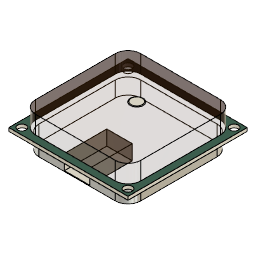
RaspberryPI5 Case + LoraWan1302 Hat (Autodesk Fusion 360 archive; units mm, degrees)
design "Beitian BE-280 GPS/GNSS Module"
Autodesk Fusion 360 part; units mm, degrees
sketch "Sketch1" plane through (0, 0, 0) normal (0, 0, 1) x (1, 0, 0)
  line L0 (0, 0) -> (28.1, 0)
  line L1 (28.1, 0) -> (28.1, 28.1)
  line L2 (28.1, 28.1) -> (0, 28.1)
  line L3 (0, 28.1) -> (0, 0)
  circle A0 centre (1.55, 26.55) radius 1
  circle A1 centre (26.55, 26.55) radius 1
  circle A2 centre (1.55, 1.55) radius 1
  circle A3 centre (26.55, 1.55) radius 1
  dimension "d1" = 28.1
  dimension "d2" = 28.1
  dimension "d3" = 2
  dimension "d4" = 2
  dimension "d5" = 2
  dimension "d6" = 2
  dimension "d7" = 25
  dimension "d8" = 25
  dimension "d9" = 25
  dimension "d10" = 25
  dimension "d11" = 1.55
  dimension "d12" = 1.55
  constraint horizontal L0
  constraint vertical L1
  constraint horizontal L2
  constraint vertical L3
  constraint coincident L0.start L3.end
  measures "d1" distance of L0.start L0.end
  measures "d2" distance of L0.start L2.end
  measures "d3" diameter of A0
  measures "d4" diameter of A1
  measures "d5" diameter of A2
  measures "d6" diameter of A3
  measures "d7" distance of A0.centre A1.centre
  measures "d8" distance of A0.centre A2.centre
  measures "d9" horizontal distance of A2.centre A3.centre
  measures "d10" distance of A1.centre A3.centre
  measures "d11" distance of L1 A1.centre
  measures "d12" distance of L2 A1.centre
extrude "Extrude1" add sketch "Sketch1" along normal blind 0.8
sketch "Sketch2" plane through (0, 0, 0.8) normal (0, 0, 1) x (-1, 0, 0)
  circle A0 centre (-26.55, -1.55) radius 1
  circle A1 centre (-1.55, -26.55) radius 1
  circle A2 centre (-26.55, -26.55) radius 1
  circle A3 centre (-1.55, -1.55) radius 1
  line L0 (0, -28.1) -> (0, 0)
  line L1 (0, 0) -> (-28.1, 0)
  line L2 (-28.1, 0) -> (-28.1, -28.1)
  line L3 (-28.1, -28.1) -> (0, -28.1)
  line L4 (-4.65, -26.45) -> (-23.45, -26.45)
  line L5 (-26.45, -23.45) -> (-26.45, -4.65)
  line L6 (-23.45, -1.65) -> (-4.65, -1.65)
  line L7 (-1.65, -4.65) -> (-1.65, -23.45)
  arc A4 (-4.65, -26.45) -> (-1.65, -23.45) centre (-4.65, -23.45) ccw
  arc A5 (-26.45, -23.45) -> (-23.45, -26.45) centre (-23.45, -23.45) ccw
  arc A6 (-23.45, -1.65) -> (-26.45, -4.65) centre (-23.45, -4.65) ccw
  arc A7 (-1.65, -4.65) -> (-4.65, -1.65) centre (-4.65, -4.65) ccw
  point P0 (-1.65, -26.45)
  point P1 (-26.45, -26.45)
  point P2 (-1.65, -1.65)
  dimension "d15" = 24.8
  dimension "d16" = 24.8
  dimension "d17" = 1.65
  dimension "d18" = 1.65
  dimension "d19" = 3
  dimension "d20" = 3
  constraint horizontal L4
  constraint vertical L5
  constraint horizontal L6
  constraint vertical L7
  constraint coincident P0 L4
  constraint coincident P0 L7
  constraint tangent L4 A4
  constraint tangent L7 A4
  constraint coincident P1 L4
  constraint coincident P1 L5
  constraint tangent L4 A5
  constraint tangent L5 A5
  constraint equal A4 A5
  constraint tangent L5 A6
  constraint tangent L6 A6
  constraint equal A4 A6
  constraint coincident P2 L6
  constraint coincident P2 L7
  constraint tangent L6 A7
  constraint tangent L7 A7
  measures "d15" distance of P0 P1
  measures "d16" distance of P0 P2
  measures "d17" distance of L3 L4
  measures "d18" distance of L0 L7
  measures "d19" radius of A4
  measures "d20" radius of A7
extrude "Extrude2" add sketch "Sketch2" along normal blind 4.2 contours L4 L5 L6 L7 A4 A5 A6 A7
sketch "Sketch3" plane through (0, 0, 5) normal (0, 0, 1) x (-1, 0, 0)
  arc A0 (-4.65, -26.45) -> (-1.65, -23.45) centre (-4.65, -23.45) ccw
  line L0 (-1.65, -23.45) -> (-1.65, -4.65)
  arc A1 (-1.65, -4.65) -> (-4.65, -1.65) centre (-4.65, -4.65) ccw
  line L1 (-4.65, -1.65) -> (-23.45, -1.65)
  arc A2 (-23.45, -1.65) -> (-26.45, -4.65) centre (-23.45, -4.65) ccw
  line L2 (-26.45, -4.65) -> (-26.45, -23.45)
  arc A3 (-26.45, -23.45) -> (-23.45, -26.45) centre (-23.45, -23.45) ccw
  line L3 (-23.45, -26.45) -> (-4.65, -26.45)
  circle A4 centre (-14.05, -16.1) radius 1.5
  line L4 (-28.1, -28.1) -> (0, -28.1)
  line L5 (-28.1, 0) -> (-28.1, -28.1)
  dimension "d23" = 3
  dimension "d24" = 12
  dimension "d25" = 14.05
  measures "d23" diameter of A4
  measures "d24" distance of A4.centre L4
  measures "d25" distance of A4.centre L5
extrude "Extrude3" add sketch "Sketch3" along normal blind 0.1 contours A4
sketch "Sketch4" plane through (0, 0, 0) normal (0, 0, -1) x (1, 0, 0)
  circle A0 centre (26.55, -1.55) radius 1
  circle A1 centre (1.55, -26.55) radius 1
  circle A2 centre (26.55, -26.55) radius 1
  circle A3 centre (1.55, -1.55) radius 1
  line L0 (0, 0) -> (0, -28.1)
  line L1 (0, -28.1) -> (28.1, -28.1)
  line L2 (28.1, -28.1) -> (28.1, 0)
  line L3 (28.1, 0) -> (0, 0)
  line L4 (23.05, -26.05) -> (5.05, -26.05)
  line L5 (2.05, -23.05) -> (2.05, -5.05)
  line L6 (5.05, -2.05) -> (23.05, -2.05)
  line L7 (26.05, -5.05) -> (26.05, -23.05)
  arc A4 (23.05, -26.05) -> (26.05, -23.05) centre (23.05, -23.05) ccw
  arc A5 (2.05, -23.05) -> (5.05, -26.05) centre (5.05, -23.05) ccw
  arc A6 (5.05, -2.05) -> (2.05, -5.05) centre (5.05, -5.05) ccw
  arc A7 (26.05, -5.05) -> (23.05, -2.05) centre (23.05, -5.05) ccw
  point P0 (26.05, -26.05)
  point P1 (2.05, -26.05)
  point P2 (26.05, -2.05)
  dimension "d28" = 24
  dimension "d29" = 24
  dimension "d30" = 2.05
  dimension "d31" = 2.05
  dimension "d32" = 3
  constraint horizontal L4
  constraint vertical L5
  constraint horizontal L6
  constraint vertical L7
  constraint coincident P0 L4
  constraint coincident P0 L7
  constraint tangent L4 A4
  constraint tangent L7 A4
  constraint coincident P1 L4
  constraint coincident P1 L5
  constraint tangent L4 A5
  constraint tangent L5 A5
  constraint equal A4 A5
  constraint tangent L5 A6
  constraint tangent L6 A6
  constraint equal A4 A6
  constraint coincident P2 L6
  constraint coincident P2 L7
  constraint tangent L6 A7
  constraint tangent L7 A7
  constraint equal A4 A7
  measures "d28" distance of P0 P1
  measures "d29" distance of P0 P2
  measures "d30" distance of L2 L7
  measures "d31" distance of L1 L4
  measures "d32" radius of A4
extrude "Extrude4" add sketch "Sketch4" along normal blind 3.7 contours L4 L5 L6 L7 A4 A5 A6 A7
sketch "Sketch5" plane through (0, 2.05, 0) normal (0, -1, 0) x (1, 0, 0)
  line L0 (23.05, 0) -> (5.05, 0)
  line L1 (5.05, 0) -> (5.05, -3.7)
  line L2 (5.05, -3.7) -> (23.05, -3.7)
  line L3 (23.05, -3.7) -> (23.05, 0)
  line L4 (17.05, 0) -> (11.05, 0)
  line L5 (11.05, 0) -> (11.05, -3.5)
  line L6 (11.05, -3.5) -> (17.05, -3.5)
  line L7 (17.05, -3.5) -> (17.05, 0)
  dimension "d35" = 6
  dimension "d36" = 3.5
  dimension "d37" = 6
  constraint horizontal L4
  constraint vertical L5
  constraint horizontal L6
  constraint vertical L7
  constraint coincident L0 L4.start
  measures "d35" distance of L4.start L4.end
  measures "d36" distance of L4.start L6.end
  measures "d37" distance of L1 L5
extrude "Extrude5" cut sketch "Sketch5" against normal blind 10 contours L0 L4 L5 L6 L7
fillet "Fillet1" radius 0.2 1 edges at (15.4485, 16.6424, 5.1)
equation "d21 = 5 mm - 0.8 mm"
equation "d25 = ( 28.1 / 2 ) * 1 mm"
equation "d33 = 4.5 mm - 0.8 mm"
named bodies: "GPSModule"
